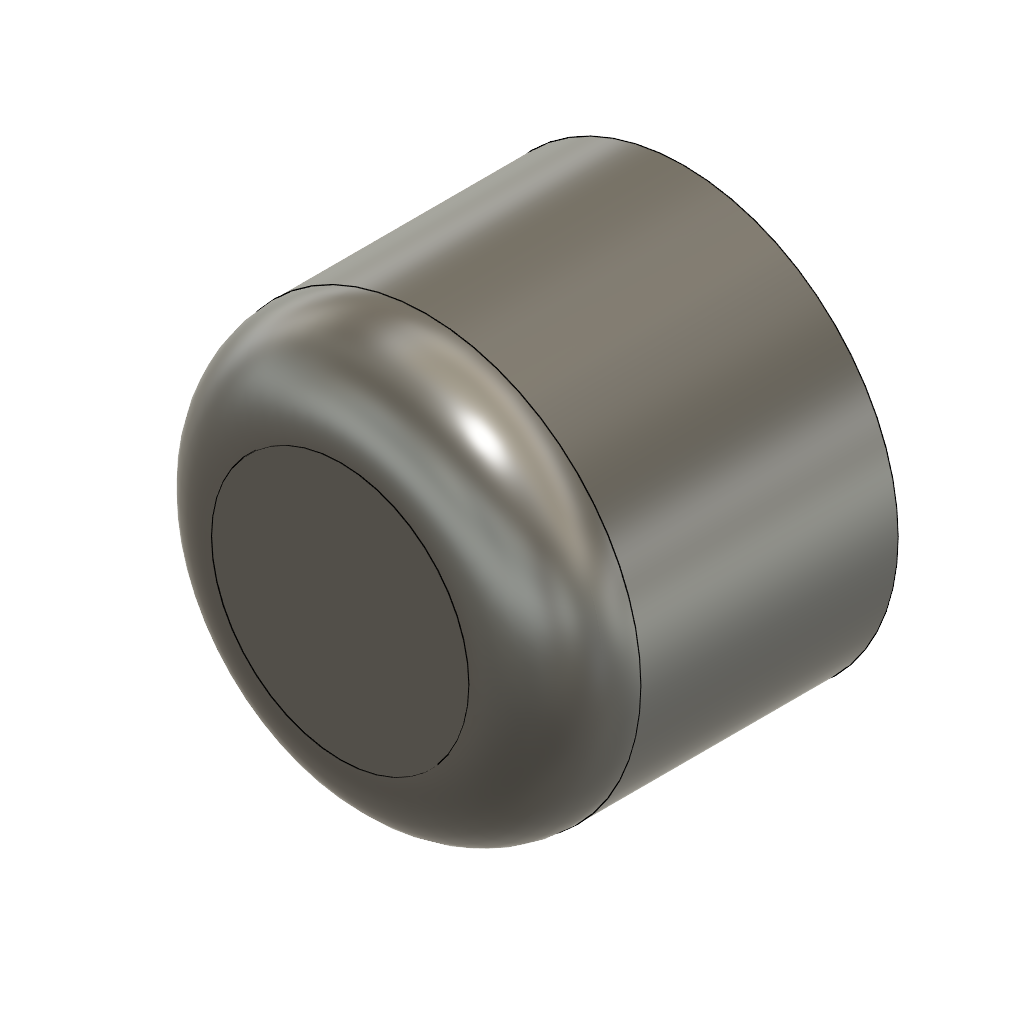
fillet_cylinder_top_edge (Autodesk Fusion 360 design; units mm, degrees)
part number: 2026-11-12-22-55-12-166
Autodesk Fusion 360 part; units mm, degrees
sketch "Sketch1" plane through (0, 0, 0) normal (0, 0, 1) x (1, 0, 0)
  circle A0 centre (0, 0) radius 5
extrude "Extrude1" add sketch "Sketch1" along normal blind 8
fillet "Fillet1" radius 2 1 edges at (-4.6616, -1.8081, 8)
